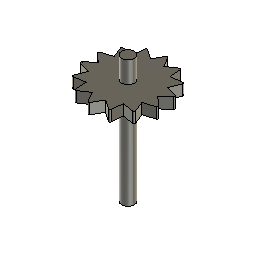
in gear 2 (Autodesk Fusion 360 design; units mm, degrees)
part number: 2026-03-27-23-33-12-431
Autodesk Fusion 360 part; units mm, degrees
sketch "Sketch1" plane through (0, 0, 0) normal (0, 0, 1) x (1, 0, 0)
  circle A0 centre (0, 0) radius 3
  dimension "d1" = 6
  constraint coincident A0.centre origin
  measures "d1" diameter of A0
extrude "Extrude1" add sketch "Sketch1" along normal blind 49.5
sketch "Sketch2" plane through (0, 0, 49.5) normal (0, 0, 1) x (-1, 0, 0)
  circle A0 centre (0, 0) radius 3
  circle A1 centre (0, 0) radius 13.5
  dimension "d4" = 27
  constraint concentric A0 A1
  measures "d4" diameter of A1
extrude "Extrude2" add sketch "Sketch2" against normal blind 5
sketch "Sketch3" plane through (0, 0, 49.5) normal (0, 0, 1) x (-1, 0, 0)
  circle A0 centre (0, 0) radius 13.5
  line L0 (-3.4641, -13.048) -> (0, -19.048)
  line L1 (0, -19.048) -> (3.4641, -13.048)
  line L2 (3.4641, -13.048) -> (-3.4641, -13.048)
  point P0 (0, -15.048)
  dimension "d7" = 2
  constraint horizontal L2
  constraint coincident A0 L1.end
  constraint coincident A0 L0.start
  measures "d7" distance of P0 L2
extrude "Extrude3" add sketch "Sketch3" against normal up to surface (5 mm away) contours A0 L0 L1
fillet "Fillet1" radius 0.5 1 edges at (0, 19.048, 47)
sketch "Sketch5" plane through (0, 0, 49.5) normal (0, 0, 1) x (-1, 0, 0)
  line L0 (-3.4641, -13.048) -> (-0.433, -18.298)
  arc A0 (-0.433, -18.298) -> (0.433, -18.298) centre (0, -18.048) ccw
  line L1 (0.433, -18.298) -> (3.4641, -13.048)
  circle A1 centre (0, 0) radius 3
  arc A2 (3.4641, -13.048) -> (-3.4641, -13.048) centre (0, 0) ccw
  constraint coincident A1.centre A2.centre
extrude "Extrude5" add sketch "Sketch5" along normal blind 10 contours A1
pattern_circular "C-Pattern2" count 14 over 360 about axis through (0, 0, 1.75) along (0, 0, 1) of "Extrude3", "Fillet1"
